Autodesk Fusion 360 part; units mm, degrees
(part 5 of 5)
  spline S40 degree 5 poles (-16.3633, 12.6343) (-16.371, 12.6403) (-16.3866, 12.652) (-16.4105, 12.669) (-16.4431, 12.6904) (-16.4849, 12.7156) (-16.5276, 12.7397) (-16.5708, 12.763) (-16.6142, 12.7859) (-16.6579, 12.8086) (-16.7017, 12.831) (-16.7458, 12.8531) (-16.7902, 12.8746) (-16.835, 12.8956) (-16.8802, 12.916) (-16.9257, 12.9359) (-16.9715, 12.9553) (-17.0176, 12.9744) (-17.0638, 12.993) (-17.1103, 13.0114) (-17.157, 13.0295) (-17.2038, 13.0472) (-17.2509, 13.0646) (-17.2982, 13.0815) (-17.3457, 13.0982) (-17.3934, 13.1145) (-17.4414, 13.1304) (-17.4895, 13.146) (-17.5378, 13.1613) (-17.5862, 13.1764) (-17.6349, 13.1911) (-17.6836, 13.2055) (-17.7326, 13.2196) (-17.7817, 13.2334) (-17.831, 13.2469) (-17.8805, 13.2601) (-17.9301, 13.2731) (-17.9798, 13.2857) (-18.0298, 13.2981) (-18.0798, 13.3102) (-18.13, 13.322) (-18.1803, 13.3335) (-18.2308, 13.3448) (-18.2814, 13.3558) (-18.3321, 13.3665) (-18.383, 13.3769) (-18.434, 13.3871) (-18.4851, 13.397) (-18.5364, 13.4067) (-18.5878, 13.4161) (-18.6393, 13.4252) (-18.6909, 13.4341) (-18.7426, 13.4428) (-18.7945, 13.4511) (-18.8465, 13.4593) (-18.8985, 13.4671) (-18.9507, 13.4748) (-19.003, 13.4821) (-19.0554, 13.4893) (-19.108, 13.4962) (-19.1606, 13.5028) (-19.2133, 13.5092) (-19.2661, 13.5153) (-19.3191, 13.5212) (-19.3721, 13.5269) (-19.4252, 13.5323) (-19.4784, 13.5375) (-19.5317, 13.5425) (-19.5851, 13.5472) (-19.6386, 13.5517) (-19.6922, 13.5559) (-19.7352, 13.5591) (-19.7674, 13.5614) (-19.7889, 13.5629) (-19.7997, 13.5636) knots 0 0 0 0 0 0 0.01428571 0.02857143 0.04285714 0.05714286 0.07142857 0.08571429 0.1 0.11428571 0.12857143 0.14285714 0.15714286 0.17142857 0.18571429 0.2 0.21428571 0.22857143 0.24285714 0.25714286 0.27142857 0.28571429 0.3 0.31428571 0.32857143 0.34285714 0.35714286 0.37142857 0.38571429 0.4 0.41428571 0.42857143 0.44285714 0.45714286 0.47142857 0.48571429 0.5 0.51428571 0.52857143 0.54285714 0.55714286 0.57142857 0.58571429 0.6 0.61428571 0.62857143 0.64285714 0.65714286 0.67142857 0.68571429 0.7 0.71428571 0.72857143 0.74285714 0.75714286 0.77142857 0.78571429 0.8 0.81428571 0.82857143 0.84285714 0.85714286 0.87142857 0.88571429 0.9 0.91428571 0.92857143 0.94285714 0.95714286 0.97142857 0.98571429 1 1 1 1 1 1
  arc A82 (-19.7997, 13.5636) -> (-20.563, 12.3759) centre (0, 0) ccw
  spline S41 degree 5 poles (-20.563, 12.3759) (-20.5579, 12.3664) (-20.5476, 12.3475) (-20.5321, 12.3191) (-20.5113, 12.2814) (-20.4852, 12.2344) (-20.4589, 12.1876) (-20.4324, 12.1409) (-20.4058, 12.0945) (-20.379, 12.0483) (-20.352, 12.0022) (-20.3248, 11.9563) (-20.2974, 11.9106) (-20.2699, 11.8651) (-20.2422, 11.8198) (-20.2143, 11.7747) (-20.1862, 11.7298) (-20.1579, 11.6851) (-20.1295, 11.6406) (-20.1009, 11.5963) (-20.0721, 11.5522) (-20.0431, 11.5083) (-20.0139, 11.4646) (-19.9846, 11.4211) (-19.9551, 11.3778) (-19.9254, 11.3348) (-19.8955, 11.292) (-19.8654, 11.2494) (-19.8351, 11.207) (-19.8047, 11.1648) (-19.774, 11.1229) (-19.7432, 11.0812) (-19.7122, 11.0397) (-19.681, 10.9985) (-19.6496, 10.9575) (-19.618, 10.9167) (-19.5862, 10.8762) (-19.5542, 10.836) (-19.522, 10.7959) (-19.4897, 10.7562) (-19.4571, 10.7167) (-19.4243, 10.6775) (-19.3914, 10.6385) (-19.3582, 10.5999) (-19.3248, 10.5615) (-19.2912, 10.5233) (-19.2574, 10.4855) (-19.2234, 10.4479) (-19.1892, 10.4107) (-19.1548, 10.3737) (-19.1202, 10.337) (-19.0853, 10.3007) (-19.0502, 10.2648) (-19.0149, 10.2291) (-18.9793, 10.1939) (-18.9435, 10.1589) (-18.9075, 10.1243) (-18.8712, 10.09) (-18.8348, 10.056) (-18.7981, 10.0224) (-18.7611, 9.9893) (-18.7238, 9.9567) (-18.6861, 9.9246) (-18.648, 9.8932) (-18.6097, 9.8622) (-18.5711, 9.8317) (-18.5323, 9.8014) (-18.4934, 9.7714) (-18.4542, 9.7418) (-18.4146, 9.713) (-18.3743, 9.6853) (-18.3413, 9.6646) (-18.3159, 9.65) (-18.2988, 9.6407) (-18.2901, 9.6361) knots -1 -1 -1 -1 -1 -1 -0.98571429 -0.97142857 -0.95714286 -0.94285714 -0.92857143 -0.91428571 -0.9 -0.88571429 -0.87142857 -0.85714286 -0.84285714 -0.82857143 -0.81428571 -0.8 -0.78571429 -0.77142857 -0.75714286 -0.74285714 -0.72857143 -0.71428571 -0.7 -0.68571429 -0.67142857 -0.65714286 -0.64285714 -0.62857143 -0.61428571 -0.6 -0.58571429 -0.57142857 -0.55714286 -0.54285714 -0.52857143 -0.51428571 -0.5 -0.48571429 -0.47142857 -0.45714286 -0.44285714 -0.42857143 -0.41428571 -0.4 -0.38571429 -0.37142857 -0.35714286 -0.34285714 -0.32857143 -0.31428571 -0.3 -0.28571429 -0.27142857 -0.25714286 -0.24285714 -0.22857143 -0.21428571 -0.2 -0.18571429 -0.17142857 -0.15714286 -0.14285714 -0.12857143 -0.11428571 -0.1 -0.08571429 -0.07142857 -0.05714286 -0.04285714 -0.02857143 -0.01428571 0 0 0 0 0 0
  line L41 (-18.2901, 9.6361) -> (-18.28, 9.6308)
  arc A83 (-17.8399, 8.3233) -> (-18.28, 9.6308) centre (-18.7461, 8.7461) ccw
  arc A84 (-17.8399, 8.3233) -> (-17.9729, 8.0319) centre (0, 0) ccw
  arc A85 (-19.2493, 7.5083) -> (-17.9729, 8.0319) centre (-18.8859, 8.4399) ccw
  line L42 (-19.2493, 7.5083) -> (-19.26, 7.5124)
  spline S42 degree 5 poles (-19.26, 7.5124) (-19.2691, 7.516) (-19.2873, 7.5228) (-19.315, 7.5324) (-19.3523, 7.5438) (-19.3996, 7.5562) (-19.4473, 7.5673) (-19.4953, 7.5775) (-19.5435, 7.5872) (-19.5917, 7.5967) (-19.6401, 7.6058) (-19.6886, 7.6146) (-19.7373, 7.6228) (-19.7862, 7.6303) (-19.8353, 7.6371) (-19.8846, 7.6434) (-19.934, 7.6491) (-19.9835, 7.6544) (-20.0332, 7.6593) (-20.083, 7.6638) (-20.1328, 7.668) (-20.1828, 7.6718) (-20.2328, 7.6752) (-20.283, 7.6782) (-20.3333, 7.6808) (-20.3837, 7.6829) (-20.4341, 7.6847) (-20.4847, 7.6862) (-20.5353, 7.6873) (-20.5861, 7.688) (-20.6369, 7.6884) (-20.6878, 7.6885) (-20.7387, 7.6883) (-20.7897, 7.6877) (-20.8408, 7.6867) (-20.892, 7.6855) (-20.9433, 7.6839) (-20.9946, 7.682) (-21.0459, 7.6798) (-21.0973, 7.6773) (-21.1488, 7.6745) (-21.2004, 7.6714) (-21.252, 7.668) (-21.3036, 7.6643) (-21.3553, 7.6603) (-21.4071, 7.656) (-21.4589, 7.6514) (-21.5108, 7.6465) (-21.5627, 7.6413) (-21.6146, 7.6359) (-21.6666, 7.6301) (-21.7186, 7.6241) (-21.7707, 7.6178) (-21.8228, 7.6113) (-21.875, 7.6044) (-21.9272, 7.5973) (-21.9794, 7.5899) (-22.0316, 7.5823) (-22.0839, 7.5743) (-22.1363, 7.5661) (-22.1886, 7.5577) (-22.241, 7.549) (-22.2934, 7.54) (-22.3459, 7.5307) (-22.3984, 7.5212) (-22.4508, 7.5115) (-22.5034, 7.5015) (-22.5559, 7.4912) (-22.6085, 7.4807) (-22.6611, 7.4699) (-22.7137, 7.4589) (-22.7558, 7.4498) (-22.7874, 7.4429) (-22.8085, 7.4383) (-22.819, 7.436) knots 0 0 0 0 0 0 0.01428571 0.02857143 0.04285714 0.05714286 0.07142857 0.08571429 0.1 0.11428571 0.12857143 0.14285714 0.15714286 0.17142857 0.18571429 0.2 0.21428571 0.22857143 0.24285714 0.25714286 0.27142857 0.28571429 0.3 0.31428571 0.32857143 0.34285714 0.35714286 0.37142857 0.38571429 0.4 0.41428571 0.42857143 0.44285714 0.45714286 0.47142857 0.48571429 0.5 0.51428571 0.52857143 0.54285714 0.55714286 0.57142857 0.58571429 0.6 0.61428571 0.62857143 0.64285714 0.65714286 0.67142857 0.68571429 0.7 0.71428571 0.72857143 0.74285714 0.75714286 0.77142857 0.78571429 0.8 0.81428571 0.82857143 0.84285714 0.85714286 0.87142857 0.88571429 0.9 0.91428571 0.92857143 0.94285714 0.95714286 0.97142857 0.98571429 1 1 1 1 1 1
  arc A86 (-22.819, 7.436) -> (-23.2167, 6.0813) centre (0, 0) ccw
  spline S43 degree 5 poles (-23.2167, 6.0813) (-23.2091, 6.0737) (-23.1939, 6.0584) (-23.1711, 6.0355) (-23.1405, 6.0052) (-23.1022, 5.9674) (-23.0638, 5.9299) (-23.0253, 5.8927) (-22.9866, 5.8556) (-22.9479, 5.8188) (-22.909, 5.7822) (-22.87, 5.7458) (-22.8308, 5.7097) (-22.7916, 5.6738) (-22.7522, 5.6382) (-22.7128, 5.6027) (-22.6732, 5.5675) (-22.6335, 5.5326) (-22.5936, 5.4979) (-22.5537, 5.4635) (-22.5136, 5.4293) (-22.4735, 5.3953) (-22.4332, 5.3616) (-22.3928, 5.3282) (-22.3523, 5.295) (-22.3116, 5.262) (-22.2709, 5.2294) (-22.23, 5.1969) (-22.189, 5.1648) (-22.1479, 5.1329) (-22.1067, 5.1013) (-22.0654, 5.07) (-22.0239, 5.039) (-21.9824, 5.0082) (-21.9407, 4.9777) (-21.8989, 4.9475) (-21.857, 4.9176) (-21.815, 4.888) (-21.7728, 4.8586) (-21.7306, 4.8296) (-21.6882, 4.8009) (-21.6457, 4.7725) (-21.6031, 4.7444) (-21.5604, 4.7167) (-21.5175, 4.6892) (-21.4746, 4.6621) (-21.4315, 4.6353) (-21.3883, 4.6089) (-21.345, 4.5827) (-21.3015, 4.5569) (-21.258, 4.5315) (-21.2143, 4.5065) (-21.1705, 4.4819) (-21.1265, 4.4577) (-21.0824, 4.4339) (-21.0382, 4.4104) (-20.9939, 4.3874) (-20.9495, 4.3646) (-20.905, 4.3423) (-20.8603, 4.3204) (-20.8155, 4.299) (-20.7705, 4.2782) (-20.7253, 4.2581) (-20.6799, 4.2387) (-20.6344, 4.2198) (-20.5887, 4.2013) (-20.543, 4.1832) (-20.4972, 4.1654) (-20.4513, 4.148) (-20.4052, 4.1315) (-20.3587, 4.1164) (-20.3211, 4.1058) (-20.2927, 4.0989) (-20.2736, 4.0948) (-20.264, 4.0929) knots -1 -1 -1 -1 -1 -1 -0.98571429 -0.97142857 -0.95714286 -0.94285714 -0.92857143 -0.91428571 -0.9 -0.88571429 -0.87142857 -0.85714286 -0.84285714 -0.82857143 -0.81428571 -0.8 -0.78571429 -0.77142857 -0.75714286 -0.74285714 -0.72857143 -0.71428571 -0.7 -0.68571429 -0.67142857 -0.65714286 -0.64285714 -0.62857143 -0.61428571 -0.6 -0.58571429 -0.57142857 -0.55714286 -0.54285714 -0.52857143 -0.51428571 -0.5 -0.48571429 -0.47142857 -0.45714286 -0.44285714 -0.42857143 -0.41428571 -0.4 -0.38571429 -0.37142857 -0.35714286 -0.34285714 -0.32857143 -0.31428571 -0.3 -0.28571429 -0.27142857 -0.25714286 -0.24285714 -0.22857143 -0.21428571 -0.2 -0.18571429 -0.17142857 -0.15714286 -0.14285714 -0.12857143 -0.11428571 -0.1 -0.08571429 -0.07142857 -0.05714286 -0.04285714 -0.02857143 -0.01428571 0 0 0 0 0 0
  line L43 (-20.264, 4.0929) -> (-20.2528, 4.0906)
  arc A87 (-19.4622, 2.96) -> (-20.2528, 4.0906) centre (-20.4508, 3.1104) ccw
  circle A88 centre (0, 0) radius 5
  circle A89 centre (0, 0) radius 5
  dimension "d9" = 10
  constraint coincident A0.centre A2.centre
  measures "d9" diameter of A89
extrude "Extrude3" add sketch "Sketch4" against normal blind 50 contours A88 A89
named bodies: "Spur Gear (22 teeth)"
